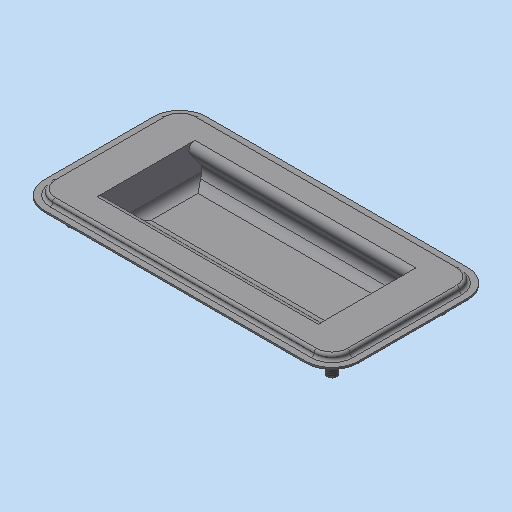
# Autodesk Inventor part: MM0858AN301_G02_385_GN 7332-155-C-1-GS
Saved by Autodesk Inventor 2023.3 (Build 273359000, 359)
## iProperties
Created: 2019-01-07
Part Number: MM0858AN301_G02_385_GN 7332-155-C-1-GS
Material: Generisch
Catalog Web Link: www.cadenas.de
Description: Edelstahl-Griffschale
Vendor: GANTER
Document SubType Name: Modeling
Designer: psadmin
Manufacturer: GANTER
Mass: 99 g
Surface Area: 368.212 cm^2
Volume: 16.0836 cm^3
Density: 1 g/cm^3
Appearance: PSOLRGB-191-191-191
Project: 0850
Category: PARTsolutions
Company: GANTER
PSOL_IDENT_0: {$CADENAS_DATA\23d-libs\ganter\data\1_2\gn7332\gn7332_c.prj},238 {VTYP=3D},{NB=Stainless Steel-Gripp
PSOL_IDENT_1: ing tray GN 7332-155-C-1-GS},{LINA=Stainless Steel-Gripping tray GN 7332-155-C-1-GS},{NN=GN 7332},{D
PSOL_IDENT_2: ATE=21.12.2018 09:09:20},{GEOMDATE=12.12.2018 07:01:05},{VERSION=},{LINEID=120},{WBVAR=},{WBNUMERIC=
PSOL_IDENT_3: }  {NB=Edelstahl-Griffschale GN 7332-155-C-1-GS},{LINA=Edelstahl-Griffschale GN 7332-155-C-1-GS},{KT=
PSOL_IDENT_4: DUMMY},{PARTNUMBER=GN 7332-155-C-1-GS},{NORMNR=GN 7332},{DIST=3.5},{L1=155},{H1=80},{H2=43},{L2=99},
PSOL_IDENT_5: {L3=25},{L4=3.5},{L5=22.5},{L6=60},{L7=115},{M1=128},{M2=53},{WEIGHT=0.0990},{CTN=73269098},{ROHS=YE
PSOL_IDENT_6: S},{INFOGANTER=Produktdetails},{INFOGANTERX=https://www.ganter-griff.com/en/products/1.2-Operating-b
PSOL_IDENT_7: y-using-machine-anddevicehandles/GN-7332-Stainless-Steel-Gripping-trays-screw-in-type},{KENNZIFFER=1
PSOL_IDENT_8: },{X=129},{OFL=SR},{FARBE=0.75,0.75,0.75,0.00}
NN: GN 7332
NT: Stainless Steel-Gripping trays, Type C with welded grub screws
NB: Stainless Steel-Gripping tray GN 7332-155-C-1-GS
NBSYN: Stainless Steel-Gripping tray $PARTNUMBER.
LINA: Stainless Steel-Gripping tray GN 7332-155-C-1-GS
PARTNUMBER: GN 7332-155-C-1-GS
L1: 155
H1: 80
H2: 43
L2: 99
L3: 25
L4: 3.5
L5: 22.5
L6: 60
L7: 115
M1: 128
M2: 53
WEIGHT: 0.099
CTN: 73269098
ROHS: YES
INFOGANTER: Product details
SUPPLIER: GANTER
ARTICLENO: Stainless Steel-Gripping tray GN 7332-155-C-1-GS
BOMINFO: Stainless Steel-Gripping tray GN 7332-155-C-1-GS
CREATOR: CADENAS GmbH
Name: MM0858AN301_G02_385_GN 7332-155-C-1-GS.ipt
RBSURFACE2: --
RBSURFACE: Stainless Steel-Gripping trays, Type C with welded grub screws
RBPARTNOTITLE1: Stainless Steel-Gripping tray
RBPARTNOTITLE2: Edelstahl-Griffschale
RBDRAWINGMISSINGSPEC: --
AnP_Kategorie: 2
AnP_Material: =<Material>
RBMATERIAL: --
RBPARTMADEOF: GN 7332-155-C-1-GS
RBMATNO: =<Part Number>
Title: Stainless Steel-Gripping tray GN 7332-155-C-1-GS
Author: Cadenas PARTsolutions
Comments: =<RBSURFACE2>
Keywords: =<RBPARTMADEOF>
Revision Number: 01
Autodesk Inventor part; units mm, degrees
ref_plane "YZ Plane" through (0, 0, 0) normal (1, 0, 0) x (0, 1, 0)
ref_plane "XZ Plane" through (0, 0, 0) normal (0, 1, 0) x (-1, 0, 0)
ref_plane "XY Plane" through (0, 0, 0) normal (0, 0, 1) x (1, 0, 0)
sketch "Sketch_1" plane through (0, 0, 0) normal (0, 0, 1) x (1, 0, 0)
  line L0 (-64.5, 34.5) -> (-64.5, -34.5)
  line L1 (-64.5, -34.5) -> (64.5, -34.5)
  line L2 (64.5, -34.5) -> (64.5, 34.5)
  line L3 (64.5, 34.5) -> (-64.5, 34.5)
  constraints: 8 end point
extrude "Extrusion1" add sketch "Sketch_1" against normal blind 0.8
sketch "Sketch_2" plane through (0, 0, 0) normal (0, 1, 0) x (-1, 0, 0)
  line L0 (58, 0) -> (-58, 0)
  line L1 (-58, 0) -> (-58, -0.8013)
  arc A0 (-55.7258, -2.9232) -> (-58, -0.8013) centre (-57.9245, -3) ccw
  line L2 (-55.7258, -2.9232) -> (-55.2981, -15.1745)
  arc A1 (-55.2981, -15.1745) -> (-50.3011, -20) centre (-50.3011, -15) ccw
  line L3 (-50.3011, -20) -> (50.3011, -20)
  arc A2 (50.3011, -20) -> (55.2981, -15.1745) centre (50.3011, -15) ccw
  line L4 (55.2981, -15.1745) -> (55.7258, -2.9232)
  arc A3 (58, -0.8013) -> (55.7258, -2.9232) centre (57.9245, -3) ccw
  line L5 (58, -0.8013) -> (58, 0)
  constraints: 12 end point, 8 point on circle, 4 centre point
extrude "Extrusion2" add sketch "Sketch_2" along normal mid plane 70
sketch "Sketch_5" plane through (0, 0, 0) normal (1, 0, 0) x (0, 1, 0)
  line L0 (-23.8254, 10) -> (-23.8254, 0)
  arc A0 (-21.6313, -0.954) -> (-23.8254, 0) centre (-23.8254, -3) ccw
  line L1 (-21.6313, -0.954) -> (-6.7745, -16.886)
  arc A1 (-6.7745, -16.886) -> (-1.4527, -19.2) centre (-1.4527, -11.9233) ccw
  line L2 (-1.4527, -19.2) -> (21.6367, -19.2)
  arc A2 (21.6367, -19.2) -> (26.5471, -17.2658) centre (21.5956, -11.8954) ccw
  arc A3 (26.5471, -17.2658) -> (27.0618, -11.6997) centre (23.6827, -14.1941) ccw
  line L3 (27.0618, -11.6997) -> (21.955, -4.7817)
  arc A4 (24.3686, 0) -> (21.955, -4.7817) centre (24.3686, -3) ccw
  line L4 (24.3686, 0) -> (24.3686, 10)
  line L5 (24.3686, 10) -> (-23.8254, 10)
  constraints: 12 end point, 10 point on circle, 5 centre point
extrude "Extrusion3" cut sketch "Sketch_5" along normal mid plane 109
sketch "Sketch_8" plane through (0, 0, 0) normal (0, 1, 0) x (-1, 0, 0)
  line L0 (55.4089, -12) -> (54.6089, -12)
  line L1 (54.6089, -12) -> (54.499, -15.1466)
  arc A0 (50.3016, -19.2) -> (54.499, -15.1466) centre (50.3016, -15) ccw
  line L2 (50.3016, -19.2) -> (-50.3016, -19.2)
  arc A1 (-54.499, -15.1466) -> (-50.3016, -19.2) centre (-50.3016, -15) ccw
  line L3 (-54.499, -15.1466) -> (-54.6089, -12)
  line L4 (-54.6089, -12) -> (-55.4089, -12)
  line L5 (-55.4089, -12) -> (-55.2981, -15.1745)
  arc A2 (-55.2981, -15.1745) -> (-50.3011, -20) centre (-50.3011, -15) ccw
  line L6 (-50.3011, -20) -> (50.3011, -20)
  arc A3 (50.3011, -20) -> (55.2981, -15.1745) centre (50.3011, -15) ccw
  line L7 (55.2981, -15.1745) -> (55.4089, -12)
  constraints: 16 end point, 8 point on circle, 4 centre point
extrude "Extrusion4" add sketch "Sketch_8" along normal mid plane 56
sketch "Sketch_9" plane through (0, 0, 0) normal (1, 0, 0) x (0, 1, 0)
  arc A0 (24.3686, -0.8) -> (22.5986, -4.3066) centre (24.3686, -3) ccw
  line L0 (22.5986, -4.3066) -> (27.7054, -11.2246)
  arc A1 (27.1059, -17.8385) -> (27.7054, -11.2246) centre (23.6827, -14.1941) ccw
  arc A2 (21.5968, -20) -> (27.1059, -17.8385) centre (21.5968, -11.8986) ccw
  line L1 (21.5968, -20) -> (-1.4527, -20)
  arc A3 (-7.3596, -17.4316) -> (-1.4527, -20) centre (-1.4527, -11.9233) ccw
  line L2 (-7.3596, -17.4316) -> (-22.2164, -1.4996)
  arc A4 (-22.2164, -1.4996) -> (-23.8254, -0.8) centre (-23.8254, -3) ccw
  line L3 (-23.8254, -0.8) -> (-58, -0.8)
  line L4 (-58, -0.8) -> (-58, -30)
  line L5 (-58, -30) -> (58, -30)
  line L6 (58, -30) -> (58, -0.8)
  line L7 (58, -0.8) -> (24.3686, -0.8)
  constraints: 16 end point, 10 point on circle, 5 centre point
extrude "Extrusion5" cut sketch "Sketch_9" along normal mid plane 155
sketch "Sketch_3" plane through (0, 0, 0) normal (1, 0, 0) x (0, 1, 0)
  line L0 (34.5, 0) -> (34.5, -0.8)
  arc A0 (35, -1.3) -> (34.5, -0.8) centre (34.5, -1.3) ccw
  line L1 (35, -1.3) -> (35, -1.4)
  arc A1 (35, -1.4) -> (37.1, -3.5) centre (37.1, -1.4) ccw
  line L2 (37.1, -3.5) -> (40, -3.5)
  line L3 (40, -3.5) -> (40, -2.7)
  line L4 (40, -2.7) -> (37.1, -2.7)
  arc A2 (35.8, -1.4) -> (37.1, -2.7) centre (37.1, -1.4) ccw
  line L5 (35.8, -1.4) -> (35.8, -1.3)
  arc A3 (35.8, -1.3) -> (34.5, 0) centre (34.5, -1.3) ccw
  constraints: 12 end point, 8 point on circle, 4 centre point
extrude "Extrusion6" add sketch "Sketch_3" along normal mid plane 129
sketch "Sketch_4" plane through (-64.5, 0, 0) normal (1, 0, 0) x (0, 0, -1)
  line L0 (0.8, 27) -> (0, 27)
  line L1 (0, 27) -> (0, 34.5)
  arc A0 (1.3, 35.8) -> (0, 34.5) centre (1.3, 34.5) ccw
  line L2 (1.3, 35.8) -> (1.4, 35.8)
  arc A1 (1.4, 35.8) -> (2.7, 37.1) centre (1.4, 37.1) ccw
  line L3 (2.7, 37.1) -> (2.7, 40)
  line L4 (2.7, 40) -> (3.5, 40)
  line L5 (3.5, 40) -> (3.5, 37.1)
  arc A2 (1.4, 35) -> (3.5, 37.1) centre (1.4, 37.1) ccw
  line L6 (1.4, 35) -> (1.3, 35)
  arc A3 (1.3, 35) -> (0.8, 34.5) centre (1.3, 34.5) ccw
  line L7 (0.8, 34.5) -> (0.8, 27)
  line L8 (0.8, 27) -> (0, 27)
  constraints: 18 end point, 8 point on circle, 4 centre point
revolve "Revolution1" add sketch "Sketch_4" angle 90 about axis through (-64.5, 27, -0.8) along (0, 0, 1)
sketch "Sketch_7" plane through (0, 0, 0) normal (0, 1, 0) x (-1, 0, 0)
  line L0 (77.5, -2.7) -> (74.6, -2.7)
  arc A0 (73.3, -1.4) -> (74.6, -2.7) centre (74.6, -1.4) ccw
  line L1 (73.3, -1.4) -> (73.3, -1.3)
  arc A1 (73.3, -1.3) -> (72, 0) centre (72, -1.3) ccw
  line L2 (72, 0) -> (64.5, 0)
  line L3 (64.5, 0) -> (64.5, -0.8)
  line L4 (64.5, -0.8) -> (72, -0.8)
  arc A2 (72.5, -1.3) -> (72, -0.8) centre (72, -1.3) ccw
  line L5 (72.5, -1.3) -> (72.5, -1.4)
  arc A3 (72.5, -1.4) -> (74.6, -3.5) centre (74.6, -1.4) ccw
  line L6 (74.6, -3.5) -> (77.5, -3.5)
  line L7 (77.5, -3.5) -> (77.5, -2.7)
  constraints: 16 end point, 8 point on circle, 4 centre point
extrude "Extrusion7" add sketch "Sketch_7" along normal mid plane 54
sketch "Sketch_10" plane through (-64.5, 0, 0) normal (1, 0, 0) x (0, 0, -1)
  line L0 (0, -27) -> (0.8, -27)
  line L1 (0.8, -27) -> (0.8, -34.5)
  arc A0 (0.8, -34.5) -> (1.3, -35) centre (1.3, -34.5) ccw
  line L2 (1.3, -35) -> (1.4, -35)
  arc A1 (3.5, -37.1) -> (1.4, -35) centre (1.4, -37.1) ccw
  line L3 (3.5, -37.1) -> (3.5, -40)
  line L4 (3.5, -40) -> (2.7, -40)
  line L5 (2.7, -40) -> (2.7, -37.1)
  arc A2 (2.7, -37.1) -> (1.4, -35.8) centre (1.4, -37.1) ccw
  line L6 (1.4, -35.8) -> (1.3, -35.8)
  arc A3 (0, -34.5) -> (1.3, -35.8) centre (1.3, -34.5) ccw
  line L7 (0, -34.5) -> (0, -27)
  line L8 (0, -27) -> (0.8, -27)
  constraints: 18 end point, 8 point on circle, 4 centre point
revolve "Revolution2" add sketch "Sketch_10" angle 90 about axis through (-64.5, -27, 0) along (0, 0, -1)
sketch "Sketch_11" plane through (0, 0, 0) normal (1, 0, 0) x (0, 1, 0)
  arc A0 (-34.5, 0) -> (-35.8, -1.3) centre (-34.5, -1.3) ccw
  line L0 (-35.8, -1.3) -> (-35.8, -1.4)
  arc A1 (-37.1, -2.7) -> (-35.8, -1.4) centre (-37.1, -1.4) ccw
  line L1 (-37.1, -2.7) -> (-40, -2.7)
  line L2 (-40, -2.7) -> (-40, -3.5)
  line L3 (-40, -3.5) -> (-37.1, -3.5)
  arc A2 (-37.1, -3.5) -> (-35, -1.4) centre (-37.1, -1.4) ccw
  line L4 (-35, -1.4) -> (-35, -1.3)
  arc A3 (-34.5, -0.8) -> (-35, -1.3) centre (-34.5, -1.3) ccw
  line L5 (-34.5, -0.8) -> (-34.5, 0)
  constraints: 12 end point, 8 point on circle, 4 centre point
extrude "Extrusion8" add sketch "Sketch_11" along normal mid plane 129
sketch "Sketch_12" plane through (64.5, 0, 0) normal (1, 0, 0) x (0, 0, -1)
  line L0 (0.8, 27) -> (0, 27)
  line L1 (0, 27) -> (0, 34.5)
  arc A0 (1.3, 35.8) -> (0, 34.5) centre (1.3, 34.5) ccw
  line L2 (1.3, 35.8) -> (1.4, 35.8)
  arc A1 (1.4, 35.8) -> (2.7, 37.1) centre (1.4, 37.1) ccw
  line L3 (2.7, 37.1) -> (2.7, 40)
  line L4 (2.7, 40) -> (3.5, 40)
  line L5 (3.5, 40) -> (3.5, 37.1)
  arc A2 (1.4, 35) -> (3.5, 37.1) centre (1.4, 37.1) ccw
  line L6 (1.4, 35) -> (1.3, 35)
  arc A3 (1.3, 35) -> (0.8, 34.5) centre (1.3, 34.5) ccw
  line L7 (0.8, 34.5) -> (0.8, 27)
  line L8 (0.8, 27) -> (0, 27)
  constraints: 18 end point, 8 point on circle, 4 centre point
revolve "Revolution3" add sketch "Sketch_12" angle 90 about axis through (64.5, 27, -0.8) along (0, 0, -1)
sketch "Sketch_13" plane through (64.5, 0, 0) normal (1, 0, 0) x (0, 0, -1)
  line L0 (0, -27) -> (0.8, -27)
  line L1 (0.8, -27) -> (0.8, -34.5)
  arc A0 (0.8, -34.5) -> (1.3, -35) centre (1.3, -34.5) ccw
  line L2 (1.3, -35) -> (1.4, -35)
  arc A1 (3.5, -37.1) -> (1.4, -35) centre (1.4, -37.1) ccw
  line L3 (3.5, -37.1) -> (3.5, -40)
  line L4 (3.5, -40) -> (2.7, -40)
  line L5 (2.7, -40) -> (2.7, -37.1)
  arc A2 (2.7, -37.1) -> (1.4, -35.8) centre (1.4, -37.1) ccw
  line L6 (1.4, -35.8) -> (1.3, -35.8)
  arc A3 (0, -34.5) -> (1.3, -35.8) centre (1.3, -34.5) ccw
  line L7 (0, -34.5) -> (0, -27)
  line L8 (0, -27) -> (0.8, -27)
  constraints: 18 end point, 8 point on circle, 4 centre point
revolve "Revolution4" add sketch "Sketch_13" angle 90 about axis through (64.5, -27, 0) along (0, 0, 1)
sketch "Sketch_14" plane through (0, 0, 0) normal (0, 1, 0) x (-1, 0, 0)
  line L0 (-64.5, -0.8) -> (-64.5, 0)
  line L1 (-64.5, 0) -> (-72, 0)
  arc A0 (-72, 0) -> (-73.3, -1.3) centre (-72, -1.3) ccw
  line L2 (-73.3, -1.3) -> (-73.3, -1.4)
  arc A1 (-74.6, -2.7) -> (-73.3, -1.4) centre (-74.6, -1.4) ccw
  line L3 (-74.6, -2.7) -> (-77.5, -2.7)
  line L4 (-77.5, -2.7) -> (-77.5, -3.5)
  line L5 (-77.5, -3.5) -> (-74.6, -3.5)
  arc A2 (-74.6, -3.5) -> (-72.5, -1.4) centre (-74.6, -1.4) ccw
  line L6 (-72.5, -1.4) -> (-72.5, -1.3)
  arc A3 (-72, -0.8) -> (-72.5, -1.3) centre (-72, -1.3) ccw
  line L7 (-72, -0.8) -> (-64.5, -0.8)
  constraints: 16 end point, 8 point on circle, 4 centre point
extrude "Extrusion9" add sketch "Sketch_14" along normal mid plane 54
sketch "Sketch_24" plane through (64, 0, 0) normal (1, 0, 0) x (0, 0, -1)
  line L0 (15.5, 26.5) -> (0.8, 26.5)
  line L1 (0.8, 26.5) -> (0.8, 30.5)
  line L2 (0.8, 30.5) -> (3.4, 30.5)
  line L3 (3.4, 30.5) -> (3.4, 29)
  line L4 (3.4, 29) -> (15.0095, 29)
  line L5 (15.0095, 29) -> (15.5, 28.5095)
  line L6 (15.5, 28.5095) -> (15.5, 26.5)
  line L7 (15.5, 26.5) -> (0.8, 26.5)
  constraints: 16 end point
revolve "Revolution5" add sketch "Sketch_24" angle 360 about axis through (64, 26.5, -15.5) along (0, 0, -1)
thread "Thread1" size "M5x0.8" class "6g" standard "ISO Metric profile" full length
sketch "Sketch_15" plane through (64, 0, 0) normal (1, 0, 0) x (0, 0, -1)
  line L0 (15.5, -26.5) -> (0.8, -26.5)
  line L1 (0.8, -26.5) -> (0.8, -22.5)
  line L2 (0.8, -22.5) -> (3.4, -22.5)
  line L3 (3.4, -22.5) -> (3.4, -24)
  line L4 (3.4, -24) -> (15.0095, -24)
  line L5 (15.0095, -24) -> (15.5, -24.4905)
  line L6 (15.5, -24.4905) -> (15.5, -26.5)
  line L7 (15.5, -26.5) -> (0.8, -26.5)
  constraints: 16 end point
revolve "Revolution6" add sketch "Sketch_15" angle 360 about axis through (64, -26.5, -15.5) along (0, 0, -1)
thread "Thread2" size "M5x0.8" class "6g" standard "ISO Metric profile" full length
sketch "Sketch_25" plane through (-64, 0, 0) normal (1, 0, 0) x (0, 0, -1)
  line L0 (15.5, -26.5) -> (0.8, -26.5)
  line L1 (0.8, -26.5) -> (0.8, -22.5)
  line L2 (0.8, -22.5) -> (3.4, -22.5)
  line L3 (3.4, -22.5) -> (3.4, -24)
  line L4 (3.4, -24) -> (15.0095, -24)
  line L5 (15.0095, -24) -> (15.5, -24.4905)
  line L6 (15.5, -24.4905) -> (15.5, -26.5)
  line L7 (15.5, -26.5) -> (0.8, -26.5)
  constraints: 16 end point
revolve "Revolution7" add sketch "Sketch_25" angle 360 about axis through (-64, -26.5, -15.5) along (0, 0, -1)
thread "Thread3" size "M5x0.8" class "6g" standard "ISO Metric profile" full length
sketch "Sketch_26" plane through (-64, 0, 0) normal (1, 0, 0) x (0, 0, -1)
  line L0 (15.5, 26.5) -> (0.8, 26.5)
  line L1 (0.8, 26.5) -> (0.8, 30.5)
  line L2 (0.8, 30.5) -> (3.4, 30.5)
  line L3 (3.4, 30.5) -> (3.4, 29)
  line L4 (3.4, 29) -> (15.0095, 29)
  line L5 (15.0095, 29) -> (15.5, 28.5095)
  line L6 (15.5, 28.5095) -> (15.5, 26.5)
  line L7 (15.5, 26.5) -> (0.8, 26.5)
  constraints: 16 end point
revolve "Revolution8" add sketch "Sketch_26" angle 360 about axis through (-64, 26.5, -15.5) along (0, 0, -1)
thread "Thread4" size "M5x0.8" class "6g" standard "ISO Metric profile" full length
sketch "Sketch_27" plane through (0, 0, 0) normal (1, 0, 0) x (0, 1, 0)
  line L0 (34.5, 1) -> (34.5, 0)
  arc A0 (35.8, -1.3) -> (34.5, 0) centre (34.5, -1.3) ccw
  line L1 (35.8, -1.3) -> (35.8, -1.4)
  arc A1 (35.8, -1.4) -> (37.1, -2.7) centre (37.1, -1.4) ccw
  line L2 (37.1, -2.7) -> (40, -2.7)
  line L3 (40, -2.7) -> (40, 1)
  line L4 (40, 1) -> (34.5, 1)
  constraints: 10 end point, 4 point on circle, 2 centre point
extrude "Extrusion10" cut sketch "Sketch_27" along normal mid plane 200
sketch "Sketch_35" plane through (0, 0, 0) normal (1, 0, 0) x (0, 1, 0)
  line L0 (-34.5, 1) -> (-40, 1)
  line L1 (-40, 1) -> (-40, -2.7)
  line L2 (-40, -2.7) -> (-37.1, -2.7)
  arc A0 (-37.1, -2.7) -> (-35.8, -1.4) centre (-37.1, -1.4) ccw
  line L3 (-35.8, -1.4) -> (-35.8, -1.3)
  arc A1 (-34.5, 0) -> (-35.8, -1.3) centre (-34.5, -1.3) ccw
  line L4 (-34.5, 0) -> (-34.5, 1)
  constraints: 10 end point, 4 point on circle, 2 centre point
extrude "Extrusion11" cut sketch "Sketch_35" along normal mid plane 200
body "Solid1"
